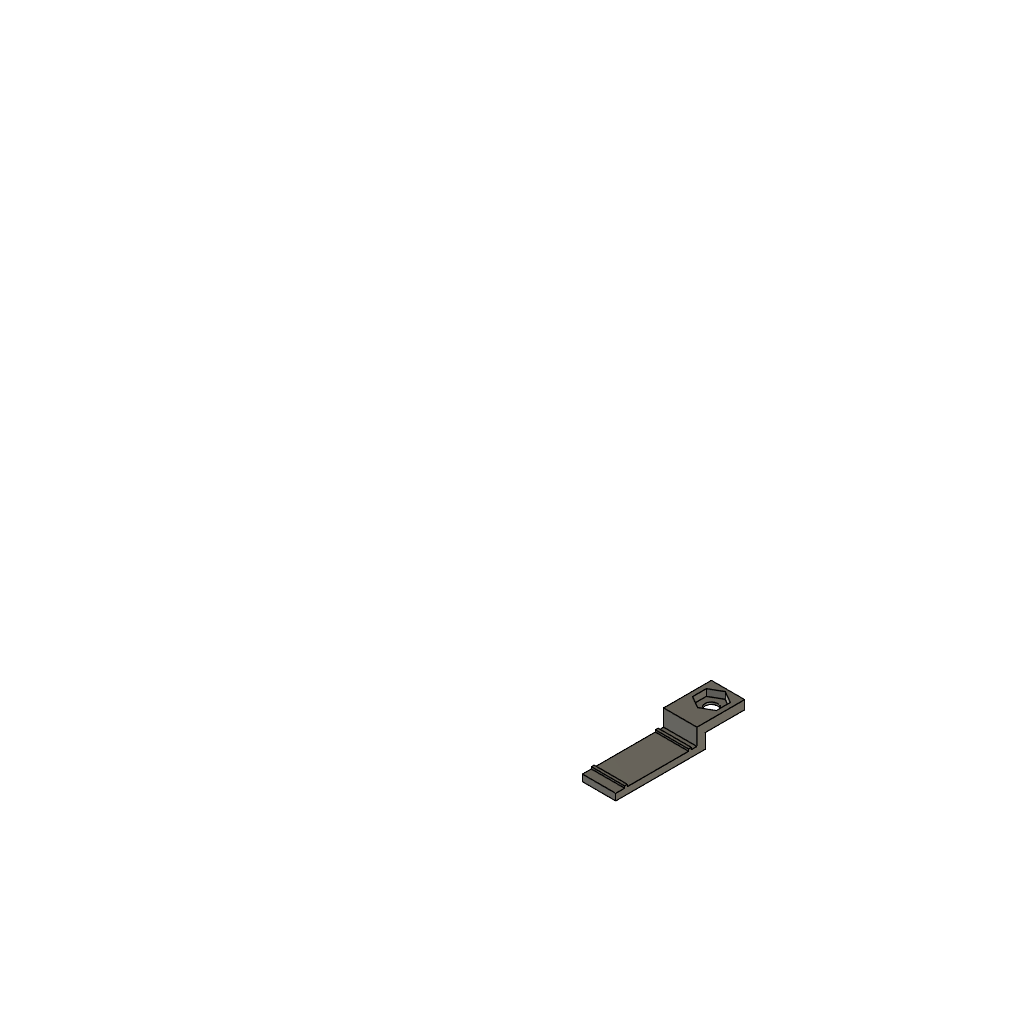
PW67_OLED_Clip_B (Autodesk Fusion 360 design; units mm, degrees)
part number: 2026-10-11-22-41-58-082
Autodesk Fusion 360 part; units mm, degrees
ref_plane "WorkPlane1" through (0, 0, 14.065) normal (0, 0, 1) x (1, 0, 0)
sketch "PCB underside clearance spine" plane through (0, 0, 14.065) normal (0, 0, 1) x (1, 0, 0)
  line L0 (99.2, -45.4) -> (105.2, -45.4)
  line L1 (105.2, -45.4) -> (105.2, -29.3)
  line L2 (105.2, -29.3) -> (99.2, -29.3)
  line L3 (99.2, -29.3) -> (99.2, -45.4)
  dimension "d210" = 6
  dimension "d211" = 16.1
  dimension "d212" = 99.2
  dimension "d213" = 45.4
  measures "d210" horizontal distance of L0.start L1.end
  measures "d211" vertical distance of L0.start L1.end
  measures "d212" horizontal distance of origin L0.start
  measures "d213" vertical distance of origin L0.start
extrude "PCB underside clearance spine (1)" add sketch "PCB underside clearance spine" along normal blind 1.2
ref_plane "WorkPlane2" through (0, 0, 15.265) normal (0, 0, 1) x (1, 0, 0)
sketch "Bare PCB retention pad" plane through (0, 0, 15.265) normal (0, 0, 1) x (1, 0, 0)
  line L0 (99.2, -43.8) -> (105.2, -43.8)
  line L1 (105.2, -43.8) -> (105.2, -43.3)
  line L2 (105.2, -43.3) -> (99.2, -43.3)
  line L3 (99.2, -43.3) -> (99.2, -43.8)
  dimension "d218" = 6
  dimension "d219" = 0.5
  dimension "d220" = 99.2
  dimension "d221" = 43.8
  measures "d218" horizontal distance of L0.start L1.end
  measures "d219" vertical distance of L0.start L1.end
  measures "d220" horizontal distance of origin L0.start
  measures "d221" vertical distance of origin L0.start
extrude "Bare PCB retention pad (1)" add sketch "Bare PCB retention pad" along normal blind 0.35
ref_plane "WorkPlane3" through (0, 0, 15.265) normal (0, 0, 1) x (1, 0, 0)
sketch "Bare PCB retention pad (1)" plane through (0, 0, 15.265) normal (0, 0, 1) x (1, 0, 0)
  line L0 (99.2, -32.3) -> (105.2, -32.3)
  line L1 (105.2, -32.3) -> (105.2, -31.8)
  line L2 (105.2, -31.8) -> (99.2, -31.8)
  line L3 (99.2, -31.8) -> (99.2, -32.3)
  dimension "d226" = 6
  dimension "d227" = 0.5
  dimension "d228" = 99.2
  dimension "d229" = 32.3
  measures "d226" horizontal distance of L0.start L1.end
  measures "d227" vertical distance of L0.start L1.end
  measures "d228" horizontal distance of origin L0.start
  measures "d229" vertical distance of origin L0.start
extrude "Bare PCB retention pad (2)" add sketch "Bare PCB retention pad (1)" along normal blind 0.35
ref_plane "WorkPlane4" through (0, 0, 15.265) normal (0, 0, 1) x (1, 0, 0)
sketch "Stepped neck above plate" plane through (0, 0, 15.265) normal (0, 0, 1) x (1, 0, 0)
  line L0 (99.2, -30.8) -> (105.2, -30.8)
  line L1 (105.2, -30.8) -> (105.2, -29.3)
  line L2 (105.2, -29.3) -> (99.2, -29.3)
  line L3 (99.2, -29.3) -> (99.2, -30.8)
  dimension "d234" = 6
  dimension "d235" = 1.5
  dimension "d236" = 99.2
  dimension "d237" = 30.8
  measures "d234" horizontal distance of L0.start L1.end
  measures "d235" vertical distance of L0.start L1.end
  measures "d236" horizontal distance of origin L0.start
  measures "d237" vertical distance of origin L0.start
extrude "Stepped neck above plate (1)" add sketch "Stepped neck above plate" along normal blind 3
ref_plane "WorkPlane5" through (0, 0, 16.665) normal (0, 0, 1) x (1, 0, 0)
sketch "M2 removable fastening tab" plane through (0, 0, 16.665) normal (0, 0, 1) x (1, 0, 0)
  line L0 (99.2, -29.4) -> (105.2, -29.4)
  line L1 (105.2, -29.4) -> (105.2, -22.2)
  line L2 (105.2, -22.2) -> (99.2, -22.2)
  line L3 (99.2, -22.2) -> (99.2, -29.4)
  dimension "d242" = 6
  dimension "d243" = 7.2
  dimension "d244" = 99.2
  dimension "d245" = 29.4
  measures "d242" horizontal distance of L0.start L1.end
  measures "d243" vertical distance of L0.start L1.end
  measures "d244" horizontal distance of origin L0.start
  measures "d245" vertical distance of origin L0.start
extrude "M2 removable fastening tab (1)" add sketch "M2 removable fastening tab" along normal blind 1.6
ref_plane "WorkPlane6" through (0, 0, 17.065) normal (0, 0, 1) x (1, 0, 0)
sketch "M2 hex nut trap - 4.3 mm AF" plane through (0, 0, 17.065) normal (0, 0, 1) x (1, 0, 0)
  line L0 (104.35, -23.9587) -> (102.2, -22.7174)
  line L1 (102.2, -22.7174) -> (100.05, -23.9587)
  line L2 (100.05, -23.9587) -> (100.05, -26.4413)
  line L3 (100.05, -26.4413) -> (102.2, -27.6826)
  line L4 (102.2, -27.6826) -> (104.35, -26.4413)
  line L5 (104.35, -26.4413) -> (104.35, -23.9587)
  circle A0 centre (102.2, -25.2) radius 2.4826 construction
  dimension "d271" = 4.9652
  dimension "d272" = 102.2
  constraint coincident L0.end L1.start
  constraint coincident L1.end L2.start
  constraint coincident L2.end L3.start
  constraint coincident L3.end L4.start
  constraint coincident L4.end L5.start
  constraint coincident L0.start L5.end
  constraint coincident L0.start A0
  constraint coincident L0.end A0
  constraint coincident L1.end A0
  constraint coincident L2.end A0
  constraint coincident L3.end A0
  constraint coincident L4.end A0
  constraint equal L0 L1
  constraint equal L0 L2
  constraint equal L0 L3
  constraint equal L0 L4
  constraint equal L0 L5
  constraint vertical L2
  measures "d271" diameter of A0
  measures "d272" horizontal distance of origin A0.centre
extrude "M2 captive nut pocket" cut sketch "M2 hex nut trap - 4.3 mm AF" along normal blind 1.3
ref_plane "WorkPlane7" through (0, 0, 16.665) normal (0, 0, 1) x (1, 0, 0)
sketch "M2 clip clearance B" plane through (0, 0, 16.665) normal (0, 0, 1) x (1, 0, 0)
  circle A0 centre (102.2, -25.2) radius 1.15
  dimension "d259" = 2.3
  dimension "d274" = 102.2
  measures "d259" diameter of A0
  measures "d274" horizontal distance of origin A0.centre
extrude "M2 clip clearance B (1)" cut sketch "M2 clip clearance B" along normal blind 1.7
equation "d208 = ( oledBracketBottomZ ) - 0 mm"
equation "d212 = oledScrewRightX - ( 6 mm ) / 2"
equation "d213 = -( -45.4 mm )"
equation "d214 = oledBracketThickness"
equation "d216 = ( oledBracketBottomZ + oledBracketThickness ) - 0 mm"
equation "d220 = oledScrewRightX - ( 6 mm ) / 2"
equation "d221 = -( -43.8 mm )"
equation "d222 = oledContactTopZ - oledBracketBottomZ - oledBracketThickness"
equation "d224 = ( oledBracketBottomZ + oledBracketThickness ) - 0 mm"
equation "d228 = oledScrewRightX - ( 6 mm ) / 2"
equation "d229 = -( -32.3 mm )"
equation "d230 = oledContactTopZ - oledBracketBottomZ - oledBracketThickness"
equation "d232 = ( oledBracketBottomZ + oledBracketThickness ) - 0 mm"
equation "d236 = oledScrewRightX - ( 6 mm ) / 2"
equation "d237 = -( -30.8 mm )"
equation "d238 = oledEarBottomZ + oledEarThickness - oledBracketBottomZ - oledBracketThickness"
equation "d240 = ( oledEarBottomZ ) - 0 mm"
equation "d244 = oledScrewRightX - 3 mm"
equation "d245 = -( oledScrewY - 4.2 mm )"
equation "d246 = oledEarThickness"
equation "d248 = ( oledEarBottomZ + oledEarThickness - oledNutDepth ) - 0 mm"
equation "d250 = oledNutDepth + 0.1 mm"
equation "d257 = ( oledEarBottomZ ) - 0 mm"
equation "d259 = oledScrewClearance"
equation "d260 = oledEarThickness + 0.1 mm"
equation "d271 = 2 * oledNutAF / sqrt(3)"
equation "d272 = oledScrewRightX"
equation "d273 = -oledScrewY"
equation "d274 = oledScrewRightX"
equation "d275 = -oledScrewY"
equation "oledPCBThickness = 1.2 mm" comment "PW67 OLED; supplier tolerances and physical module must be verified"
equation "oledFrameBottomZ = 16.365 mm" comment "PW67 OLED; supplier tolerances and physical module must be verified"
equation "oledRecessDepth = 0.6 mm" comment "PW67 OLED; supplier tolerances and physical module must be verified"
equation "oledPCBTopZ = oledFrameBottomZ + oledRecessDepth" comment "PW67 OLED; supplier tolerances and physical module must be verified"
equation "oledBracketThickness = 1.2 mm" comment "PW67 OLED; supplier tolerances and physical module must be verified"
equation "oledBracketBottomZ = 14.065 mm" comment "PW67 OLED; supplier tolerances and physical module must be verified"
equation "oledRetentionGap = 0.15 mm" comment "PW67 OLED; supplier tolerances and physical module must be verified"
equation "oledContactTopZ = oledPCBTopZ - oledPCBThickness - oledRetentionGap" comment "PW67 OLED; supplier tolerances and physical module must be verified"
equation "oledScrewRightX = 102.2 mm" comment "PW67 OLED; supplier tolerances and physical module must be verified"
equation "oledScrewY = -25.2 mm" comment "PW67 OLED; supplier tolerances and physical module must be verified"
equation "oledScrewClearance = 2.3 mm" comment "PW67 OLED; supplier tolerances and physical module must be verified"
equation "oledEarBottomZ = 16.665 mm" comment "PW67 OLED; supplier tolerances and physical module must be verified"
equation "oledEarThickness = 1.6 mm" comment "PW67 OLED; supplier tolerances and physical module must be verified"
equation "oledNutAF = 4.3 mm" comment "PW67 OLED; supplier tolerances and physical module must be verified"
equation "oledNutDepth = 1.2 mm" comment "PW67 OLED; supplier tolerances and physical module must be verified"
named bodies: "Removable OLED retainer B"
